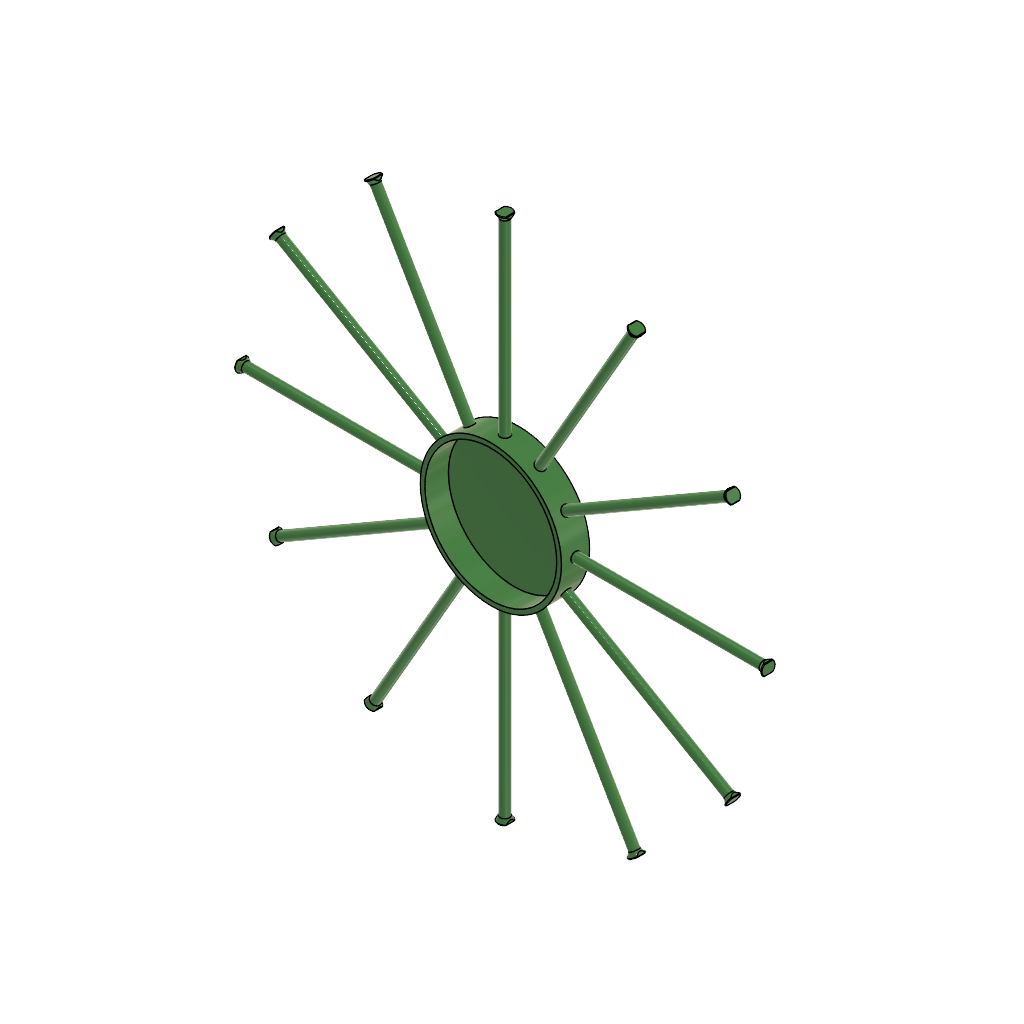
patte (Autodesk Fusion 360 design; units mm, degrees)
part number: 2026-11-27-08-09-07-575
Autodesk Fusion 360 part; units mm, degrees
sketch "Esquisse1" plane through (0, 0, 0) normal (0, 1, 0) x (1, 0, 0)
  circle A0 centre (0, 0) radius 15
  dimension "d1" = 30
  constraint coincident A0.centre origin
  measures "d1" diameter of A0
extrude "Extrusion1" add sketch "Esquisse1" along normal mid plane 6
shell "Coque1" thickness 1 removed faces 1 at (3.8315, -3, -5.6199)
sketch "Esquisse2" plane through (0, 3, 0) normal (0, 1, 0) x (-1, 0, 0)
  circle A0 centre (0, 0) radius 15
  circle A1 centre (0, 0) radius 2.5
  circle A2 centre (0, 0) radius 3.5
  dimension "d5" = 5
  dimension "d6" = 7
  constraint coincident A0.centre A1.centre
  constraint concentric A1 A2
  measures "d5" diameter of A1
  measures "d6" diameter of A2
extrude "Extrusion2" add sketch "Esquisse2" along normal blind 3 contours A2
ref_plane "Plan de construction1" through (0, -1.1036, 15) normal (0, 0, 1) x (-1, 0, 0)
sketch "Esquisse3" plane through (0, 0, 15) normal (0, 0, 1) x (1, 0, 0)
  circle A0 centre (0, 0) radius 1
  dimension "d11" = 2
  constraint coincident A0.centre origin
  measures "d11" diameter of A0
extrude "Extrusion3" add sketch "Esquisse3" along normal blind 40
sketch "Esquisse5" plane through (0, 0, 55) normal (0, 0, 1) x (-1, 0, 0)
  circle A0 centre (0, 0) radius 1
  circle A1 centre (0, 0) radius 1
  constraint coincident A0.centre A1.centre
extrude "Extrusion4" add sketch "Esquisse5" along normal blind 1 draft 30
ref_plane "Plan de construction2" through (1.5774, 0, 56) normal (0, -1, 0) x (0, 0, 1)
sketch "Esquisse6" plane through (1.5774, 0, 56) normal (0, -1, 0) x (0, 0, 1)
  line L0 (0, 0.4) -> (-0.7, 0.4)
  line L1 (-0.7, 0.4) -> (-0.7, -0.1)
  line L2 (-0.7, -0.1) -> (0.1, -0.1)
  line L3 (0.1, -0.1) -> (0.1, 0.4)
  line L4 (0.1, 0.4) -> (0, 0.4)
  constraint horizontal L0
  constraint perpendicular L0 L1
  constraint perpendicular L1 L2
  constraint perpendicular L0 L3
  constraint perpendicular L3 L4
extrude "Extrusion5" cut sketch "Esquisse6" along normal mid plane 20
mirror "Symétrie miroir1" about plane through (0, 0, 0) normal (1, 0, 0) of "Extrusion5"
fillet "Congé1" radius 0.1 4 edges at (0, -1.5774, 56) (1.1774, 0, 56) (0, 1.5774, 56) (-1.1774, 0, 56)
pattern_circular "Réseau C1" count 12 over 360 about axis through (0, -3, 0) along (0, -1, 0) of "Extrusion3", "Extrusion4", "Extrusion5", "Symétrie miroir1", "Congé1"
